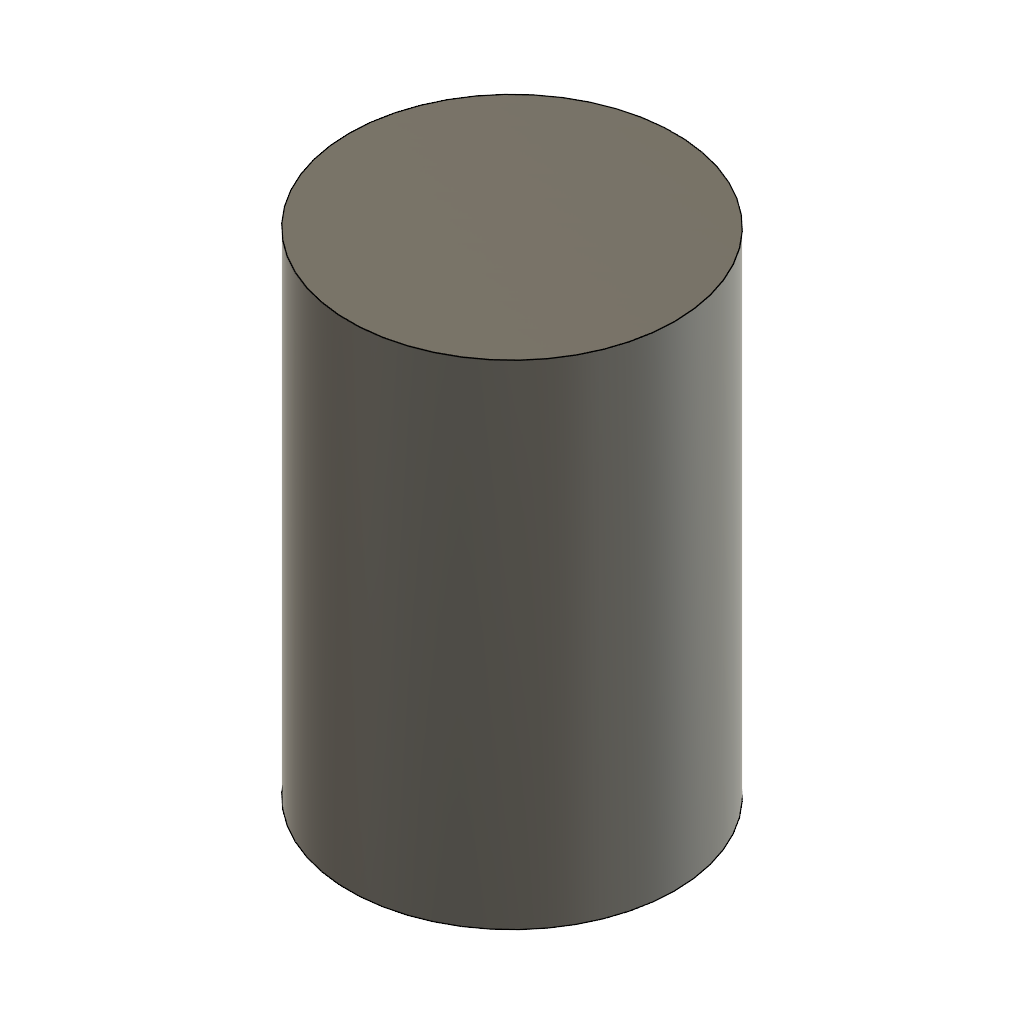
holdout_d (Autodesk Fusion 360 design; units mm, degrees)
part number: 2026-11-27-17-36-52-876
Autodesk Fusion 360 part; units mm, degrees
sketch "CircularProfile" plane through (0, 0, 0) normal (0, 1, 0) x (1, 0, 0)
  circle A0 centre (31, -29) radius 23
extrude "OffsetTwoSides" add sketch "CircularProfile" along normal blind 67.25 and the other way blind 2.375 from surface at 89
